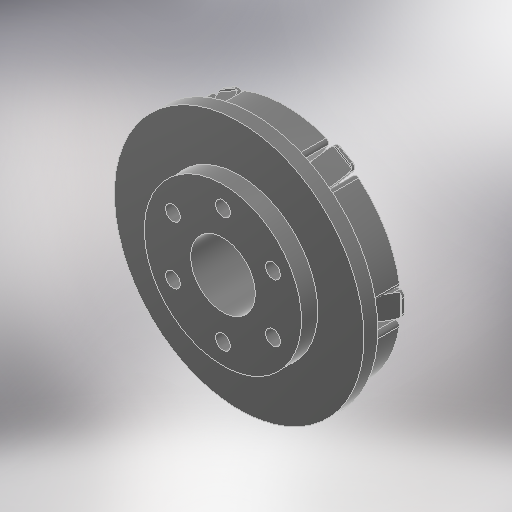
# Autodesk Inventor part: 3D_sub-motor
Saved by Autodesk Inventor 2025.3 (Build 293356030, 356C)
## iProperties
Created: 2026-02-11
Part Number: 3D_sub-motor
Material: 一般
Document SubType Name: Modeling
Designer: ibuki_ono
Density: 1 g/cm^3
Appearance: 滑らか - 黒
Author: ibuki_ono
## iProperties of the stored document 3D_sub-motor_3D プリント.ipt
Created: 2026-06-04
Part Number: 3D_sub-motor_3D プリント
Material: 一般
Document SubType Name: Modeling
Designer: ibuki_ono
Density: 1 g/cm^3
Appearance: 既定
Author: ibuki_ono
Autodesk Inventor part; units mm, degrees
ref_plane "YZ Plane" through (0, 0, 0) normal (1, 0, 0) x (0, 1, 0)
ref_plane "XZ Plane" through (0, 0, 0) normal (0, 1, 0) x (-1, 0, 0)
ref_plane "XY Plane" through (0, 0, 0) normal (0, 0, 1) x (1, 0, 0)
sketch "スケッチ1" plane through (0, 0, 0) normal (0, 0, 1) x (1, 0, 0)
  circle A0 centre (0, 0) radius 25
  dimension "d0" = 50
  constraints: 1 centre point, 1 coincident
  measures "d0" diameter of A0
extrude "押し出し1" add sketch "スケッチ1" along normal mid plane 10
sketch "スケッチ2" plane through (0, 0, 5) normal (0, 0, 1) x (1, 0, 0)
  circle A0 centre (0, 0) radius 17
  dimension "d3" = 34
  constraints: 1 centre point, 1 coincident
  measures "d3" diameter of A0
extrude "押し出し2" add sketch "スケッチ2" along normal blind 3.5
sketch "スケッチ3" plane through (0, 0, 5) normal (0, 0, 1) x (1, 0, 0)
  circle A0 centre (0, 0) radius 25 projected
  circle A1 centre (0, 0) radius 27
  dimension "d6" = 2
  constraints: 1 centre point
  measures "d6" radial gap between concentric circles of A0 A1
extrude "押し出し3" add sketch "スケッチ3" against normal blind 3
sketch "スケッチ4" plane through (0, 0, -5) normal (0, 0, -1) x (-1, 0, 0)
  circle A0 centre (0, 0) radius 25 projected
  line L0 (24.8747, 2.5) -> (19.8747, 2.5)
  line L1 (19.8747, 2.5) -> (19.8747, -2.5)
  line L2 (19.8747, -2.5) -> (24.8747, -2.5)
  line L3 (24.8747, -2.5) -> (24.8747, 2.5)
  line L4 (24.8071, -3.1) -> (19.8747, -3.1)
  line L5 (19.8747, 3.1) -> (24.8071, 3.1)
  line L6 (19.8747, 3.1) -> (19.8747, -3.1)
  point P0 (24.8747, 0)
  point P1 (19.8747, -2.5)
  point P2 (19.8747, 2.5)
  dimension "d9" = 5
  dimension "d10" = 5
  dimension "d11" = 0.6
  dimension "d12" = 0.6
  constraints: 14 end point, 4 point on circle, 3 parallel, 2 vertical alignment, 1 horizontal, 1 horizontal alignment, 1 midpoint, 1 perpendicular, 1 vertical
  measures "d9" distance of L2.end L0.start
  measures "d10" distance of L1.end L2.end
  measures "d11" distance between parallel lines of L2 L4
  measures "d12" distance between parallel lines of L5 L0
extrude "押し出し4" cut sketch "スケッチ4" against normal blind 6 contours L0 L6 L5 A0 | A0 L4 L6 L2
sketch "スケッチ5" plane through (0, 0, 0) normal (0, 1, 0) x (-1, 0, 0)
  line L0 (24.8071, -5) -> (19.8747, -5) projected
  line L1 (24.8071, 1) -> (24.8071, -5) projected
  line L2 (24.8071, 1) -> (19.8747, 1) projected
  line L3 (19.8747, -5) -> (19.8747, 1) projected
  line L4 (25, -5) -> (25, 2) projected
  line L5 (24.8747, -5) -> (25, -5) projected
  line L6 (19.8747, -5) -> (24.8747, -5) projected
  line L7 (24.8071, 1) -> (25, 1)
  line L8 (24.8071, -5) -> (22.4071, -0.8431)
  line L9 (22.4071, -0.8431) -> (24.2501, 1)
  line L10 (23.4214, -5) -> (20.9074, -0.6456)
  line L11 (20.9074, -0.6456) -> (22.5531, 1)
  point P0 (0, 0)
  dimension "d15" = 60
  dimension "d16" = 45
  dimension "d17" = 2.4
  dimension "d18" = 1.2
  constraints: 10 end point, 4 point on line, 1 perpendicular, 1 other
  measures "d15" angle of L0 L8
  measures "d16" angle of L2 L9
  measures "d17" distance from line of L1 L8.end
  measures "d18" distance between parallel lines of L8 L10
extrude "押し出し5" cut sketch "スケッチ5" along normal mid plane 5 contours L8 L9 L2 L1 | L1 L7 L4 L5 L6 | L0 L3 L2 L11 L10
sketch "スケッチ6" plane through (0, 0, 0) normal (0, 1, 0) x (-1, 0, 0)
  line L0 (23.4214, -5) -> (24.8071, -5) projected
  line L1 (23.4214, -5) -> (25.2214, -5)
  line L2 (25.2214, -5) -> (25.2214, -5.8)
  line L3 (25.2214, -5.8) -> (23.4214, -5.8)
  line L4 (23.4214, -5.8) -> (23.4214, -5)
  line L5 (23.4214, -5) -> (23.8833, -5.8)
  line L6 (23.4214, -5) -> (20.9074, -0.6456) projected
  point P0 (0, 0)
  dimension "d21" = 1.8
  dimension "d22" = 0.8
  constraints: 10 end point, 2 parallel, 1 collinear, 1 horizontal, 1 perpendicular, 1 point on line
  measures "d21" distance of L2.end L3.end
  measures "d22" distance of L1.end L2.end
extrude "押し出し6" add sketch "スケッチ6" along normal mid plane 5 contours L0 L1 L2 L3 L5
fillet "フィレット1" radius 1 2 edges at (-25.2214, 2.5, -5.4) (-25.2214, -2.5, -5.4)
chamfer "面取り1" distance 0.2 angle 45 5 edges at (-25.2214, 0, -5.8) (-24.9285, 2.2071, -5.8) (-24.0524, 2.5, -5.8) (-24.9285, -2.2071, -5.8) (-24.0524, -2.5, -5.8)
fillet "フィレット2" radius 0.8 4 edges at (-19.8747, -3.1, -2) (-19.8747, 3.1, -2) (-24.8071, 3.1, -2) (-24.8071, -3.1, -2)
chamfer "面取り3" distance 0.4 angle 45 1 edges at (-22.5531, 0, 1)
pattern_circular "円形状パターン1" count 6 over 360 about axis through (0, 0, 5) along (0, 0, -1) of "押し出し4", "押し出し5", "押し出し6", "フィレット1", "面取り1", "フィレット2", "面取り3"
sketch "スケッチ7" plane through (0, 0, 8.5) normal (0, 0, 1) x (1, 0, 0)
  line L0 (0, 0) -> (0, -12.5) construction
  line L1 (0, 0) -> (12.5, 0) construction
  dimension "d33" = 12.5
  dimension "d34" = 90
  constraints: 4 end point, 1 coincident, 1 horizontal, 1 perpendicular, 1 vertical
  measures "d33" distance of L0.start L0.end
  measures "d34" angle of L0 L1
hole "穴1" at (0, -12.5, 8.5) direction (0, 0, -1) diameter 3.2 end through all
sketch "スケッチ8" plane through (0, 0, -5) normal (0, 0, -1) x (-1, 0, 0)
  circle A0 centre (0, -12.5) radius 1.6 projected
  line L0 (-3.1754, -12.5) -> (-1.5877, -9.75)
  line L1 (-1.5877, -9.75) -> (1.5877, -9.75)
  line L2 (1.5877, -9.75) -> (3.1754, -12.5)
  line L3 (3.1754, -12.5) -> (1.5877, -15.25)
  line L4 (1.5877, -15.25) -> (-1.5877, -15.25)
  line L5 (-1.5877, -15.25) -> (-3.1754, -12.5)
  point P0 (0, 0)
  dimension "d42" = 5.5
  constraints: 12 end point, 1 coincident, 1 horizontal alignment, 13 other
  measures "d42" distance between parallel lines of L1 L4
extrude "押し出し7" cut sketch "スケッチ8" against normal blind 10
chamfer "面取り2" distance 0.8 angle 45 6 edges at (2.3816, -11.125, -5) (0, -9.75, -5) (-2.3816, -11.125, -5) (-2.3816, -13.875, -5) (0, -15.25, -5) (2.3816, -13.875, -5)
pattern_circular "円形状パターン2" count 6 over 360 about axis through (0, 0, 5) along (0, 0, -1) of "穴1", "押し出し7", "面取り2"
sketch "スケッチ9" plane through (0, 0, 8.5) normal (0, 0, 1) x (1, 0, 0)
  circle A0 centre (0, 0) radius 7
  dimension "d51" = 14
  constraints: 1 centre point, 1 coincident
  measures "d51" diameter of A0
extrude "押し出し8" cut sketch "スケッチ9" against normal through all
equation "\"d12\" = d11"
